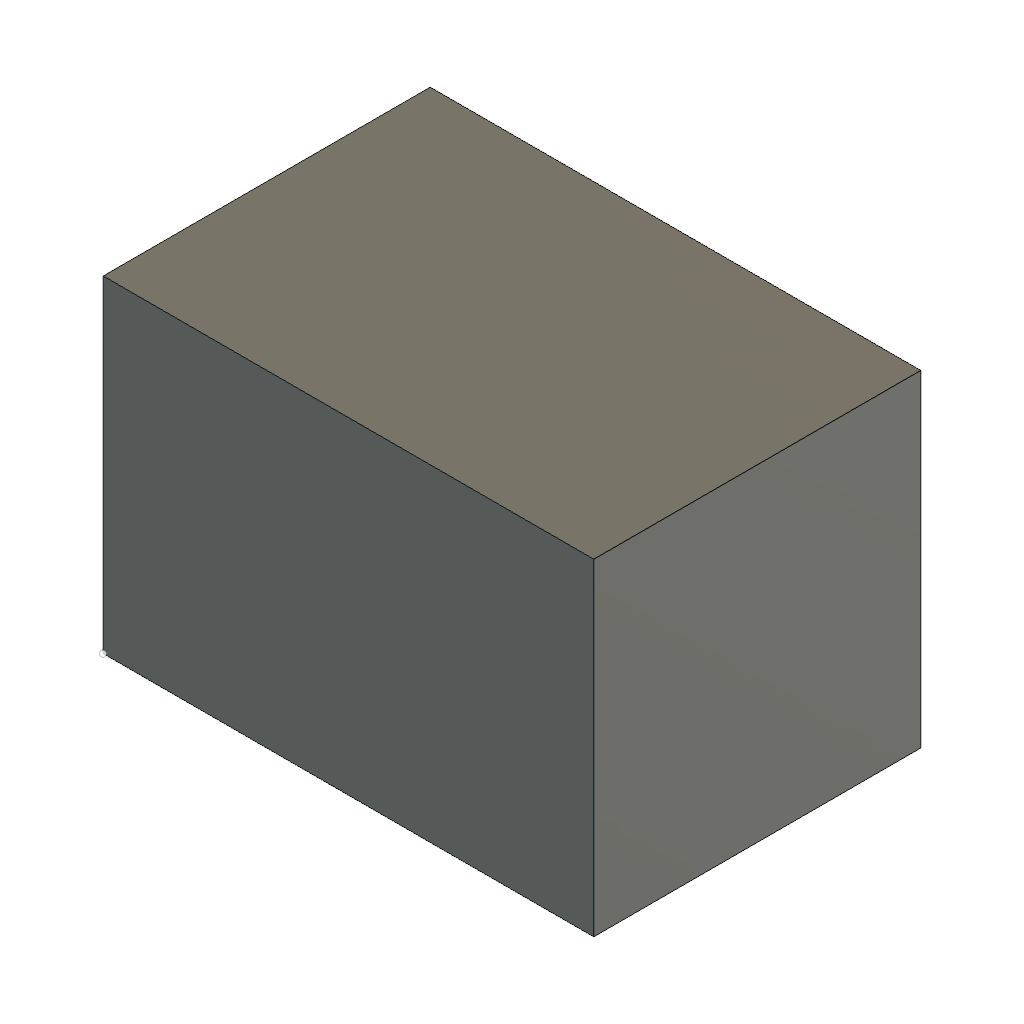
axis_perpendicular_at_point (Autodesk Fusion 360 design; units mm, degrees)
part number: 2026-10-20-21-37-13-761
Autodesk Fusion 360 part; units mm, degrees
sketch "SupportSketch" plane through (0, 0, 0) normal (0, 0, 1) x (1, 0, 0)
  line L0 (0, 0) -> (30, 0)
  line L1 (30, 0) -> (30, 20)
  line L2 (30, 20) -> (0, 20)
  line L3 (0, 20) -> (0, 0)
extrude "SeedExtrusion" add sketch "SupportSketch" along normal blind 20
sketch "AxisPoint" plane through (0, 0, 20) normal (0, 0, 1) x (1, 0, 0)
  line L0 (0, 20) -> (0, 0)
  line L1 (0, 0) -> (30, 0)
  line L2 (30, 0) -> (30, 20)
  line L3 (30, 20) -> (0, 20)
named bodies: "SupportBody"
